Autodesk Fusion 360 part; units mm, degrees
(part 2 of 3)
sketch "SLOT - J-FRONT-02 SPIGOT (MIDDLE)" plane through (0, 0, 0) normal (0, 0, 1) x (1, 0, 0) in component "352108 FRONT - DECOR FRAME DL - RING BOTTOM - FRONT FACET"
  line L0 (-1081.329, -778.1952) -> (-1076.4372, -780.7094)
  line L1 (-1076.4372, -780.7094) -> (-1072.5517, -773.1495)
  line L2 (-1072.5517, -773.1495) -> (-1077.4434, -770.6353)
  line L3 (-1077.4434, -770.6353) -> (-1081.329, -778.1952)
  point P0 (-5000, -5000)
  dimension "d3654" = 5000
  dimension "d3655" = 5000
  dimension "d3656" = 3918.671
  dimension "d3657" = 3923.5628
  dimension "d3658" = 3927.4483
  dimension "d3659" = 3922.5566
  dimension "d3660" = 4221.8048
  dimension "d3661" = 4219.2906
  dimension "d3662" = 4226.8505
  dimension "d3663" = 4229.3647
  measures "d3654" horizontal distance of origin P0
  measures "d3655" vertical distance of origin P0
  measures "d3656" horizontal distance of L0.start P0
  measures "d3657" horizontal distance of L0.end P0
  measures "d3658" horizontal distance of L1.end P0
  measures "d3659" horizontal distance of L2.end P0
  measures "d3660" vertical distance of L0.start P0
  measures "d3661" vertical distance of L0.end P0
  measures "d3662" vertical distance of L1.end P0
  measures "d3663" vertical distance of L2.end P0
extrude "CUT - J-FRONT-02 SLOT MIDDLE" cut sketch "SLOT - J-FRONT-02 SPIGOT (MIDDLE)" along normal blind 3 from surface at 109 bodies 16 in component "352108 FRONT - DECOR FRAME DL - RING BOTTOM - FRONT FACET"
component "351101 FRONT - DECOR SKIN - DL" placed x (1, 0, 0) y (0, 1, 0) z (0, 0, 1) at (0, 0, 0)
component "351102 FRONT - DECOR BACK PLATE - DL" placed x (1, 0, 0) y (0, 1, 0) z (0, 0, 1) at (0, 0, 0)
component "351105 FRONT - DOOR HINGE-SIDE STOP - DL - PIECE 1" placed x (1, 0, 0) y (0, 1, 0) z (0, 0, 1) at (0, 0, 0)
component "351106 FRONT - DOOR HINGE-SIDE STOP - DL - PIECE 2 AND 3" placed x (1, 0, 0) y (0, 1, 0) z (0, 0, 1) at (0, 0, 0)
component "351106 FRONT - DOOR HINGE-SIDE STOP - DL - PIECE 2 AND 3" placed x (1, 0, 0) y (0, 1, 0) z (0, 0, 1) at (0, 0, 754.5)
component "351107 FRONT - DOOR HINGE-SIDE STOP - DL - PIECE 4" placed x (1, 0, 0) y (0, 1, 0) z (0, 0, 1) at (0, 0, 0)
component "368005 FRONT - FRAME-STOP SEAL - HINGE SIDE 1" placed x (1, 0, 0) y (0, 1, 0) z (0, 0, 1) at (0, 0, 0)
component "368005 FRONT - FRAME-STOP SEAL - HINGE SIDE 2 AND 3" placed x (1, 0, 0) y (0, 1, 0) z (0, 0, 1) at (0, 0, 0)
component "368005 FRONT - FRAME-STOP SEAL - HINGE SIDE 2 AND 3" placed x (1, 0, 0) y (0, 1, 0) z (0, 0, 1) at (0, 0, 754.5)
component "368005 FRONT - FRAME-STOP SEAL - HINGE SIDE 4" placed x (1, 0, 0) y (0, 1, 0) z (0, 0, 1) at (0, 0, 0)
component "351104 FRONT - DECOR FRAME - DL" placed x (1, 0, 0) y (0, 1, 0) z (0, 0, 1) at (0, 0, 0)
component "352101 FRONT - DECOR FRAME DL - BACK RING BOTTOM" placed x (1, 0, 0) y (0, 1, 0) z (0, 0, 1) at (0, 0, 0) in component "351104 FRONT - DECOR FRAME - DL"
component "352102 FRONT - DECOR FRAME DL - BACK RING DOOR SIDE" placed x (1, 0, 0) y (0, 1, 0) z (0, 0, 1) at (0, 0, 0) in component "351104 FRONT - DECOR FRAME - DL"
component "352103 FRONT - DECOR FRAME DL - BACK RING SLOPE UNDER DT" placed x (1, 0, 0) y (0, 1, 0) z (0, 0, 1) at (0, 0, 0) in component "351104 FRONT - DECOR FRAME - DL"
component "352104 FRONT - DECOR FRAME DL - BACK RING BOLT LINE" placed x (1, 0, 0) y (0, 1, 0) z (0, 0, 1) at (0, 0, 0) in component "351104 FRONT - DECOR FRAME - DL"
component "352105 FRONT - DECOR FRAME DL - RING DOOR SIDE - RINGS 1 TO 4" placed x (1, 0, 0) y (0, 1, 0) z (0, 0, 1) at (0, 0, 0) in component "351104 FRONT - DECOR FRAME - DL"
component "352106 FRONT - DECOR FRAME DL - RING BACK - RINGS 1 TO 4" placed x (1, 0, 0) y (0, 1, 0) z (0, 0, 1) at (0, 0, 0) in component "351104 FRONT - DECOR FRAME - DL"
component "352107 FRONT - DECOR FRAME DL - RING BOTTOM - OUTER FACET" placed x (1, 0, 0) y (0, 1, 0) z (0, 0, 1) at (0, 0, 0) in component "351104 FRONT - DECOR FRAME - DL"
component "352108 FRONT - DECOR FRAME DL - RING BOTTOM - FRONT FACET" placed x (1, 0, 0) y (0, 1, 0) z (0, 0, 1) at (0, 0, 0) in component "351104 FRONT - DECOR FRAME - DL"
component "352105 FRONT - DECOR FRAME DL - RING DOOR SIDE - RINGS 1 TO 4" placed x (1, 0, 0) y (0, 1, 0) z (0, 0, 1) at (0, 0, 612.25) in component "351104 FRONT - DECOR FRAME - DL"
component "352106 FRONT - DECOR FRAME DL - RING BACK - RINGS 1 TO 4" placed x (1, 0, 0) y (0, 1, 0) z (0, 0, 1) at (0, 0, 612.25) in component "351104 FRONT - DECOR FRAME - DL"
component "352109 FRONT - DECOR FRAME DL - RING OUTER FACET - RINGS 2 TO 4" placed x (1, 0, 0) y (0, 1, 0) z (0, 0, 1) at (0, 0, 0) in component "351104 FRONT - DECOR FRAME - DL"
component "352110 FRONT - DECOR FRAME DL - RING FRONT FACET - RINGS 2 TO 4" placed x (1, 0, 0) y (0, 1, 0) z (0, 0, 1) at (0, 0, 0) in component "351104 FRONT - DECOR FRAME - DL"
component "352105 FRONT - DECOR FRAME DL - RING DOOR SIDE - RINGS 1 TO 4" placed x (1, 0, 0) y (0, 1, 0) z (0, 0, 1) at (0, 0, 1366.75) in component "351104 FRONT - DECOR FRAME - DL"
component "352106 FRONT - DECOR FRAME DL - RING BACK - RINGS 1 TO 4" placed x (1, 0, 0) y (0, 1, 0) z (0, 0, 1) at (0, 0, 1366.75) in component "351104 FRONT - DECOR FRAME - DL"
component "352109 FRONT - DECOR FRAME DL - RING OUTER FACET - RINGS 2 TO 4" placed x (1, 0, 0) y (0, 1, 0) z (0, 0, 1) at (0, 0, 754.5) in component "351104 FRONT - DECOR FRAME - DL"
component "352110 FRONT - DECOR FRAME DL - RING FRONT FACET - RINGS 2 TO 4" placed x (1, 0, 0) y (0, 1, 0) z (0, 0, 1) at (0, 0, 754.5) in component "351104 FRONT - DECOR FRAME - DL"
component "352105 FRONT - DECOR FRAME DL - RING DOOR SIDE - RINGS 1 TO 4" placed x (1, 0, 0) y (0, 1, 0) z (0, 0, 1) at (0, 0, 1991.7434) in component "351104 FRONT - DECOR FRAME - DL"
component "352106 FRONT - DECOR FRAME DL - RING BACK - RINGS 1 TO 4" placed x (1, 0, 0) y (0, 1, 0) z (0, 0, 1) at (0, 0, 1991.7434) in component "351104 FRONT - DECOR FRAME - DL"
component "352109 FRONT - DECOR FRAME DL - RING OUTER FACET - RINGS 2 TO 4" placed x (1, 0, 0) y (0, 1, 0) z (0, 0, 1) at (0, 0, 1379.4934) in component "351104 FRONT - DECOR FRAME - DL"
component "352110 FRONT - DECOR FRAME DL - RING FRONT FACET - RINGS 2 TO 4" placed x (1, 0, 0) y (0, 1, 0) z (0, 0, 1) at (0, 0, 1379.4934) in component "351104 FRONT - DECOR FRAME - DL"
component "352111 FRONT - DECOR FRAME DL - HINGE POST 1" placed x (1, 0, 0) y (0, 1, 0) z (0, 0, 1) at (0, 0, 0) in component "351104 FRONT - DECOR FRAME - DL"
component "352112 FRONT - DECOR FRAME DL - DOOR-SIDE FRONT POST 1" placed x (1, 0, 0) y (0, 1, 0) z (0, 0, 1) at (0, 0, 0) in component "351104 FRONT - DECOR FRAME - DL"
component "352113 FRONT - DECOR FRAME DL - HINGE POST 2" placed x (1, 0, 0) y (0, 1, 0) z (0, 0, 1) at (0, 0, 0) in component "351104 FRONT - DECOR FRAME - DL"
component "352114 FRONT - DECOR FRAME DL - DOOR-SIDE FRONT POST 2" placed x (1, 0, 0) y (0, 1, 0) z (0, 0, 1) at (0, 0, 0) in component "351104 FRONT - DECOR FRAME - DL"
component "352115 FRONT - DECOR FRAME DL - HINGE POST 3" placed x (1, 0, 0) y (0, 1, 0) z (0, 0, 1) at (0, 0, 0) in component "351104 FRONT - DECOR FRAME - DL"
component "352116 FRONT - DECOR FRAME DL - DOOR-SIDE FRONT POST 3" placed x (1, 0, 0) y (0, 1, 0) z (0, 0, 1) at (0, 0, 0) in component "351104 FRONT - DECOR FRAME - DL"
equation "pod_w = 2500 mm" comment "SKELETON P04 DECIDED: D-01; conventions s4 (X = +-1250)"
equation "pod_d = 1700 mm" comment "SKELETON P04 DECIDED: D-01; conventions s4 (Y = +-850)"
equation "pod_h = 2400 mm" comment "SKELETON P04 DECIDED: D-21 (room floor to roof skin top)"
equation "glide_h = 10 mm" comment "SKELETON P04 ASSUMPTION: layout study inputs.py glide_h"
equation "band_h = 100 mm" comment "SKELETON P04 SOURCE: layout study B1 list B-BAND 100x40; inputs.py base_h"
equation "band_t = 40 mm" comment "SKELETON P04 SOURCE: layout study B1 list B-BAND 100x40"
equation "skin_t = 3 mm" comment "SKELETON P04 DECIDED: ACP skin, walls and ceiling (D-16; PM ruling 2026-10-31 on outer_t)"
equation "bond_t = 3 mm" comment "SKELETON P04 DECIDED: bond line between the ACP and the frame (PM ruling 2026-10-31 on outer_t)"
equation "frame_t = 40 mm" comment "SKELETON P04 DECIDED: aluminium frame tube depth, walls and ceiling (PM ruling 2026-10-31 on outer_t)"
equation "outer_t = skin_t + bond_t + frame_t" comment "SKELETON P04 DECIDED: PM ruling 2026-10-31: ACP 3 + bond line 3 + frame 40, walls and ceiling (was 43)"
equation "cav_gap = 4 mm" comment "SKELETON P04 DECIDED: D-16, D-42: the gap between the outer panel and the lining cassette in the wall and ceiling stack"
equation "cass_t = 34 mm" comment "SKELETON P04 SOURCE: layout study B1 final list L-CASS 34 (tray + 25 gap + felt 9)"
equation "stack_t = outer_t + cav_gap + cass_t" comment "SKELETON P04 CALCULATION: D-16, D-42 stack, walls and ceiling: outer panel + cavity gap + cassette (PM ruling 2026-10-31 on outer_t)"
equation "wall_depth = 1495 mm" comment "SKELETON P04 DECIDED: PM ruling pass C: side walls start at the decor back plate (Y -645), as v1 (1496)"
equation "lin_gap = 4 mm" comment "SKELETON P04 ASSUMPTION: PM ruling pass C: gap above the upper side linings so they stay floating (= the 4 mm stack gap)"
equation "seam_gap = 2.26 mm" comment "SKELETON P04 DECIDED: PM ruling 2026-10-31 (Mechanical Checker F-001, F-005): the Joints Engineer's 2.26 mm at all nine site seam types, set by a metal stop (1.5 stop washer + 0.76 rivnut head; joints register section 2.8)"
equation "mat_t = 3 mm" comment "SKELETON P04 DECIDED: D-72, PM ruling 2026-10-31 (from BASE): the 3 mm floor mat under the floor ply"
equation "floor_t = 9 mm" comment "SKELETON P04 DECIDED: PM ruling 2026-10-31: 9 mm floor panels (was 15, layout study B1 list), on the mat"
equation "thresh_h = 13 mm" comment "SKELETON P04 DECIDED: PM ruling 2026-10-31: 13 mm, a US-accessible threshold (D-18 had 20); the kick strip keeps its kick_gap above it"
equation "thresh_d = 60 mm" comment "SKELETON P04 SOURCE: layout study B1 list B-THRESH 1176 x 60 x 20"
equation "decor_d = 205 mm" comment "SKELETON P04 SOURCE: v1 geometry per the PM ruling on D-39 (as v1; the drawings win): v1 decor-frame drawing frames 191 (left) and 197 (right) deep plus ACP and back plate = the v1 STEP shell, Y -850 to -645 = 205. D-39 and the B1 list say 230-235 (v1 BOM); see BUILD-RECORD-P02"
equation "dl_w = 278 mm" comment "SKELETON P04 SOURCE: B1 list F-DL 278 (v1 BOM DL)"
equation "dr_w = 1016 mm" comment "SKELETON P04 SOURCE: B1 list F-DR 1016 (v1 STEP solid 78)"
equation "dt_w = 1697 mm" comment "SKELETON P04 SOURCE: B1 list F-DT 1697 (v1 BOM DT)"
equation "dt_h = 280 mm" comment "SKELETON P04 SOURCE: B1 list F-DT 280"
equation "door_w = 1176 mm" comment "SKELETON P04 DECIDED: D-46"
equation "door_h = 2011 mm" comment "SKELETON P04 SOURCE: B1 list F-GLASS-DOOR 2011; v1 STEP solid 238"
equation "glass_t = 8.76 mm" comment "SKELETON P04 DECIDED: D-46 (4+4 laminate)"
equation "glass_y = 699 mm" comment "SKELETON P04 SOURCE: v1 STEP solid 238 centre Y = -699 (layout study data)"
equation "kick_d = 20 mm" comment "SKELETON P04 ASSUMPTION: kick strip envelope depth (D-40 gives the height only)"
equation "kick_gap = 7 mm" comment "SKELETON P04 SOURCE: FRONT door unit: 7 mm running gap between the threshold and the kick strip for the drop seal (Mechanical Checker F-002 on P03)"
equation "fr_dz = 17 mm" comment "SKELETON P04 CALCULATION: v1 front top 2417 (v2 frame) - pod_h 2400"
equation "door_xl = 289 mm" comment "SKELETON P04 SOURCE: V1-FRONT-FACETS: door left edge X -961 = -1250 + 289"
equation "door_xbr = 1464 mm" comment "SKELETON P04 SOURCE: V1-FRONT-FACETS: door bottom-right X 214"
equation "door_xtr = 1182 mm" comment "SKELETON P04 SOURCE: V1-FRONT-FACETS: door top-right X -68"
equation "door_zb = 122 mm - fr_dz" comment "SKELETON P04 SOURCE: V1-FRONT-FACETS: door bottom Z 122"
equation "door_zt = 2133 mm - fr_dz" comment "SKELETON P04 SOURCE: V1-FRONT-FACETS: door top Z 2133"
equation "glass_gap = 4 mm" comment "SKELETON P04 DECIDED: PM ruling 2026-10-31 on Mechanical Checker F-014: the fixed glass's free edge runs parallel to the door's slanted edge, 4.0 mm away (FRONT's glass in PR #28 is the reference)"
equation "fix_xbr = 302 mm" comment "SKELETON P04 SOURCE: V1-FRONT-FACETS: fixed glass bottom-right X 948 = 1250 - 302"
equation "fix_xk = 501 mm" comment "SKELETON P04 SOURCE: V1-FRONT-FACETS: fixed glass knee X 749 = 1250 - 501"
equation "fix_zk = 1538 mm - fr_dz" comment "SKELETON P04 SOURCE: V1-FRONT-FACETS: fixed glass knee Z 1538"
equation "fix_xtr = 1480 mm" comment "SKELETON P04 SOURCE: V1-FRONT-FACETS: fixed glass top-right X 230 = -1250 + 1480"
equation "fix_zb = 119 mm - fr_dz" comment "SKELETON P04 SOURCE: V1-FRONT-FACETS: fixed glass bottom Z 119"
equation "fix_zt = 2136 mm - fr_dz" comment "SKELETON P04 SOURCE: V1-FRONT-FACETS: fixed glass top Z 2136"
equation "dt_zb = 2137 mm - fr_dz" comment "SKELETON P04 SOURCE: V1-FRONT-FACETS: DT and DR edge above the glass Z 2137"
equation "ch_zlo = 2217 mm - fr_dz" comment "SKELETON P04 SOURCE: V1-FRONT-FACETS: top chamfer front edge Z 2217 at Y -848"
equation "ch_yb = 672 mm" comment "SKELETON P04 SOURCE: V1-FRONT-FACETS: top chamfer back edge Y -672"
equation "dl_x2 = 92 mm" comment "SKELETON P04 SOURCE: V1-FRONT-FACETS: DL facet knee X -1158 = -1250 + 92"
equation "dl_y2 = 752 mm" comment "SKELETON P04 SOURCE: V1-FRONT-FACETS: DL facet knee Y -752"
equation "dl_x3 = 271 mm" comment "SKELETON P04 SOURCE: V1-FRONT-FACETS: DL front corner X -979"
equation "dl_y3 = 844 mm" comment "SKELETON P04 SOURCE: V1-FRONT-FACETS: DL front corner Y -844"
equation "dl_y1 = 670 mm" comment "SKELETON P04 SOURCE: V1-FRONT-FACETS: DL outer facet start Y -670"
equation "dl_zo = 2414 mm - fr_dz" comment "SKELETON P04 SOURCE: V1-FRONT-FACETS: DL top at the outer corner Z 2414"
equation "dt_x2 = 281 mm" comment "SKELETON P04 SOURCE: V1-FRONT-FACETS: DT lower facet left X -969 = -1250 + 281"
equation "dt_y2 = 767 mm" comment "SKELETON P04 SOURCE: V1-FRONT-FACETS: DT lower facet left Y -767"
equation "dt_y3 = 753 mm" comment "SKELETON P04 SOURCE: V1-FRONT-FACETS: DT lower facet outer Y -753 at X -1154"
equation "dr_xc = 198 mm" comment "SKELETON P04 SOURCE: V1-FRONT-FACETS: DR corner facet front X 1052 = 1250 - 198"
equation "dt_xr = 1699 mm" comment "SKELETON P04 SOURCE: V1-FRONT-FACETS: DT/DR joint at the top, X 449 = -1250 + 1699 (PM ruling pass C)"
equation "dr_yc = 672 mm" comment "SKELETON P04 SOURCE: V1-FRONT-FACETS: DR corner facet back Y -672"
equation "fix_xbl = door_xbr + ( door_zb - fix_zb ) * ( door_xbr - door_xtr ) / ( door_zt - door_zb ) + glass_gap * sqrt(( door_xbr - door_xtr ) * ( door_xbr - door_xtr ) + ( door_zt - door_zb ) * ( door_zt - door_zb )) / ( door_zt - door_zb )" comment "SKELETON P04 CALCULATION: F-014: fixed glass bottom-left, on the line glass_gap from the door's slanted edge (was v1's 1468)"
equation "fix_xtl = door_xbr + ( door_zb - fix_zt ) * ( door_xbr - door_xtr ) / ( door_zt - door_zb ) + glass_gap * sqrt(( door_xbr - door_xtr ) * ( door_xbr - door_xtr ) + ( door_zt - door_zb ) * ( door_zt - door_zb )) / ( door_zt - door_zb )" comment "SKELETON P04 CALCULATION: F-014: fixed glass top-left, on the same line (was v1's 1184)"
equation "floor_top = mat_t + floor_t" comment "SKELETON P04 CALCULATION: D-72: the floor top, Z 12 (mat 3 + ply 9); the threshold stands thresh_h above the room floor"
equation "wall_z0 = glide_h + band_h" comment "SKELETON P04 CALCULATION: base band top: glides + band"
equation "panel_z0 = wall_z0 + seam_gap" comment "SKELETON P04 CALCULATION: walls stand one seam_gap above the band top (joints register 2.8, IF-01)"
equation "wall_h = pod_h - wall_z0" comment "SKELETON P04 CALCULATION: 2290 = layout study v2_model wall_h"
equation "side_h = ( wall_h - 2 * seam_gap ) / 2" comment "SKELETON P04 CALCULATION: D-23: 2 sheets per side wall; the gap on the band and the horizontal seam (joints register 2.8)"
equation "side_l = wall_depth - seam_gap" comment "SKELETON P04 CALCULATION: side panel length along Y: the seam_gap at the decor's back plate (joints register 2.8, IF-07)"
equation "back_oh = pod_h - outer_t - seam_gap - panel_z0" comment "SKELETON P04 CALCULATION: PM ruling 2026-10-31 (pass D, F-004): the back outer frames run up to the ceiling frame (pod_h - outer_t), less the seam_gap under it, closing the slot at the back top edge"
equation "back_ph = ( back_oh - seam_gap ) / 2" comment "SKELETON P04 CALCULATION: D-23: 4 sheets on the back, two equal rows with one seam_gap between them (joints register 2.8); the lower back linings match the lower row, as on the side walls"
equation "half_pw = ( pod_w - 2 * outer_t - 3 * seam_gap ) / 2" comment "SKELETON P04 CALCULATION: SKIN width of each back and ceiling panel: two skins and three seam_gap seams between the side frames (F-001, joints register 2.8)"
equation "close_gap = 5.5 mm" comment "SKELETON P04 DECIDED: PM ruling 2026-10-31 (joints register, F-011/F-012): frame gap at the closing seams B1-B2, B3-B4 and C1-C2, which have no hard stop (slotted holes, thicker gasket)"
equation "half_fw = ( pod_w - 2 * outer_t - 2 * seam_gap - close_gap ) / 2" comment "SKELETON P04 CALCULATION: FRAME width of each back and ceiling panel: the skins overhang their frames by half_pw - half_fw at the closing seam (PM ruling 2026-10-31)"
equation "inner_w = pod_w - 2 * stack_t" comment "SKELETON P04 CALCULATION: inside width between the side linings"
equation "bolt_edge_inset = 220 mm" comment "SKELETON P04 DECIDED: PM ruling 2026-10-31: on every bolted edge the end bolts sit this far in from each panel end (the FRAME end, where the bolts go), the rest evenly spaced"
equation "spigot_inset = 100 mm" comment "SKELETON P04 DECIDED: PM ruling 2026-10-31: locating spigots this far in from each panel end (round hole at one end, slot at the other)"
equation "base_bolt_edge = bolt_edge_inset" comment "SKELETON P04 DECIDED: J-BASE-01 wall to band: the edge rule (kept by this name for parts already linked)"
equation "n_base_bolt = 4" comment "SKELETON P04 DECIDED: PM ruling 2026-10-31, J-BASE-01: bolts per panel along the band, evenly spaced"
equation "base_spigot_inset = spigot_inset" comment "SKELETON P04 DECIDED: J-BASE-01: the spigot rule (kept by this name for parts already linked)"
equation "base_side_y0 = pod_d / 2 - wall_depth + seam_gap" comment "SKELETON P04 CALCULATION: J-BASE-01: side bolt lines start at the side panel's front end (first bolt base_bolt_edge further on)"
equation "side_base_pitch = ( side_l - 2 * base_bolt_edge ) / ( n_base_bolt - 1 )" comment "SKELETON P04 CALCULATION: J-BASE-01 bolt pitch along a side panel"
equation "base_back_x0 = pod_w / 2 - outer_t - seam_gap" comment "SKELETON P04 CALCULATION: J-BASE-01: back bolt lines start at each back FRAME's outer end, X -/+ this (first bolt base_bolt_edge further in)"
equation "back_base_pitch = ( half_fw - 2 * base_bolt_edge ) / ( n_base_bolt - 1 )" comment "SKELETON P04 DECIDED: PM ruling 2026-10-31 (Reviewer 5 P2 on #58): J-BASE-01 pitch along a back panel, measured on the FRAME (half_fw), where the bolts go; 'panel end' means the frame end"
equation "ceil_bolt_z = pod_h - outer_t + frame_t / 2" comment "SKELETON P04 DECIDED: PM ruling 2026-10-31, J-CEIL-01 wall to ceiling: the bolt line on the ceiling frame's centre (Z 2374)"
equation "n_ceil_side_bolt = 4" comment "SKELETON P04 DECIDED: PM ruling 2026-10-31, J-CEIL-01: bolts along each side wall top"
equation "n_ceil_back_bolt = 4" comment "SKELETON P04 DECIDED: PM ruling 2026-10-31, J-CEIL-01: bolts along each back panel top, like the base (pitch about 253, every edge 350 or less; joints register: 82 bolts in all)"
equation "ceil_side_y0 = pod_d / 2 - wall_depth" comment "SKELETON P04 DECIDED: PM ruling 2026-10-31 (joints register): J-CEIL-01 side bolt lines start at Y -645, measured along the ceiling (first bolt bolt_edge_inset further on)"
equation "ceil_side_pitch = ( wall_depth - 2 * bolt_edge_inset ) / ( n_ceil_side_bolt - 1 )" comment "SKELETON P04 DECIDED: PM ruling 2026-10-31 (joints register): J-CEIL-01 pitch along a side wall top, over the ceiling's length (was over the side panel's)"
equation "ceil_back_x0 = pod_w / 2 - outer_t - seam_gap" comment "SKELETON P04 DECIDED: PM ruling 2026-10-31 (joints register): J-CEIL-01 back bolt lines start at each back frame's outer end, X -/+ this"
equation "ceil_back_pitch = ( half_fw - 2 * bolt_edge_inset ) / ( n_ceil_back_bolt - 1 )" comment "SKELETON P04 DECIDED: PM ruling 2026-10-31 (joints register): J-CEIL-01 pitch along a back panel top, on the frame (half_fw)"
equation "sk_ref = 5000 mm" comment "ASSUMPTION: sketch reference point offset: every sketch corner is dimensioned from a point at -sk_ref on both plane axes, so no dimension changes side when a corner crosses a pod centre line in an edit"
equation "fg_vis_zb = wall_z0" comment "CALCULATION: visible bottom of the fixed pane = the base band top (DL and DR stop there too, PM ruling 2026-10-31)"
equation "fg_vis_zt = dt_zb" comment "CALCULATION: visible top of the fixed pane = DT's underside"
equation "fg_gap = glass_gap" comment "CALCULATION: = the skeleton's glass_gap: the pane's free edge runs parallel to the door's latch edge, 4 mm off (PM ruling 2026-10-31; the skeleton's fix_xbl and fix_xtl follow the same rule since its update #58)"
equation "gu_prof_w = 15 mm" comment "SOURCE: Bohle BO5201571 aluminium U-profile 15 x 15 x 1.5 (hardware selection C5)"
equation "gu_prof_d = 15 mm" comment "SOURCE: as gu_prof_w"
equation "gu_prof_t = 1.5 mm" comment "SOURCE: as gu_prof_w"
equation "gu_w = gu_prof_w - 2 * gu_prof_t" comment "CALCULATION: inner width of the U-profile = the U-seal's outer width"
equation "gu_base = 2 mm" comment "ASSUMPTION: U-seal base under the glass edge; HOLD for Bohle's BO5201735 section drawing"
equation "gu_in_d = gu_prof_d - gu_prof_t" comment "CALCULATION: inner depth of the U-profile"
equation "fg_bite = gu_in_d - gu_base" comment "CALCULATION: glass cover in the hidden channels, 11.5 (PM ruling 2026-10-31); HOLD for the glass supplier's minimum"
equation "fg_r_len = sqrt(( fix_xbr - fix_xk ) * ( fix_xbr - fix_xk ) + ( fix_zk - fix_zb ) * ( fix_zk - fix_zb ))" comment "CALCULATION: length of the skeleton's right edge (bottom-right corner to the knee)"
equation "fg_rnx = ( fix_zk - fix_zb ) / fg_r_len" comment "CALCULATION: right edge outward normal, X"
equation "fg_rnz = ( fix_xk - fix_xbr ) / fg_r_len" comment "CALCULATION: right edge outward normal, Z"
equation "fg_rc = fg_rnx * ( pod_w / 2 - fix_xbr ) + fg_rnz * fix_zb" comment "CALCULATION: right edge line constant"
equation "fg_d_len = sqrt(( pod_w - fix_xtr - fix_xk ) * ( pod_w - fix_xtr - fix_xk ) + ( dt_zb - fix_zk ) * ( dt_zb - fix_zk ))" comment "CALCULATION: length of DR's diagonal inner edge (knee to DT's underside at X -pod_w/2 + fix_xtr)"
equation "fg_dnx = ( dt_zb - fix_zk ) / fg_d_len" comment "CALCULATION: diagonal outward normal, X"
equation "fg_dnz = ( pod_w - fix_xtr - fix_xk ) / fg_d_len" comment "CALCULATION: diagonal outward normal, Z"
equation "fg_dc = fg_dnx * ( pod_w / 2 - fix_xk ) + fg_dnz * fix_zk" comment "CALCULATION: diagonal line constant"
equation "fg_det = fg_rnx * fg_dnz - fg_rnz * fg_dnx" comment "CALCULATION: for the knee corner"
equation "fg_l_len = sqrt(( door_xbr - door_xtr ) * ( door_xbr - door_xtr ) + ( door_zt - door_zb ) * ( door_zt - door_zb ))" comment "CALCULATION: length of the door's latch edge"
equation "fg_lnx = ( door_zt - door_zb ) / fg_l_len" comment "CALCULATION: door latch edge normal toward the pane, X"
equation "fg_lnz = ( door_xbr - door_xtr ) / fg_l_len" comment "CALCULATION: door latch edge normal toward the pane, Z"
equation "fg_lc = fg_lnx * ( -pod_w / 2 + door_xbr ) + fg_lnz * door_zb" comment "CALCULATION: door latch edge line constant"
equation "jf_x = pod_w / 2 - skin_t - bond_t - frame_t / 2" comment "CALCULATION: joints register J-FRONT-01: the side panel's front member centre line, X -/+1224 (skin, bond line and half the 40 frame in from the outside, skeleton named values)"
equation "jf_hole = 9.53 mm" comment "SOURCE: rivnut 838003 (Sherex CAH2-610-4.2, zinc-plated steel, D-131) hole 9.53 +0.10/0, as the aluminium part's (joints register H-03; unverified for the steel part, HOLD-04)"
equation "jf_z1 = panel_z0 + bolt_edge_inset" comment "CALCULATION: lower panel, bottom bolt (220 rule)"
equation "jf_z2 = panel_z0 + side_h / 2" comment "CALCULATION: lower panel, middle bolt"
equation "jf_z3 = panel_z0 + side_h - bolt_edge_inset" comment "CALCULATION: lower panel, top bolt"
equation "jf_z4 = panel_z0 + side_h + seam_gap + bolt_edge_inset" comment "CALCULATION: upper panel, bottom bolt"
equation "jf_z5 = panel_z0 + side_h + seam_gap + side_h / 2" comment "CALCULATION: upper panel, middle bolt"
equation "jf_z6 = panel_z0 + 2 * side_h + seam_gap - bolt_edge_inset" comment "CALCULATION: upper panel, top bolt"
equation "dl_skin_t = 3 mm" comment "SOURCE: ACP 3 mm, EV3038 Dark Yellow (D-12; hardware selection A1)"
equation "dl_fo = dl_skin_t + bond_t" comment "CALCULATION: a frame tube's face from the skin's outer face: the 3 mm ACP and the 3 mm bond line (skeleton bond_t; the bond spec's joint, at least 12 wide x 3 thick, D-137), so every tube that bonds to the skin stands 3 mm off it (PM ruling 2026-11-01)"
equation "dl_back_t = 2 mm" comment "SOURCE: joints register J-FRONT-01: the back plate is aluminium 1.0 to 2.7 thick at each bolt, for the rivnuts (HOLD-10)"
equation "door_top_cut = 2 mm" comment "DECIDED: PM ruling 2026-10-31: the leaf 2 mm short of the skeleton top (catch gap)"
equation "leaf_zt = door_zt - door_top_cut" comment "CALCULATION: top of the door leaf"
equation "hinge_clamp_h = 120 mm" comment "ASSUMPTION: reserved height per hinge; HOLD H01 (as the door unit)"
equation "hinge_clamp_t = 40 mm" comment "ASSUMPTION: reserved thickness across the glass; HOLD H01 (as the door unit)"
equation "hinge_pocket_d = 160 mm" comment "SOURCE: the HOLD candidate's 160 mm frame pocket in DL (D-30, D-46)"
equation "hinge_x0 = -pod_w / 2 + dl_w - hinge_pocket_d" comment "CALCULATION: inner end of the hinge pocket"
equation "hinge_z1 = door_zb + 250 mm" comment "ASSUMPTION: as the door unit; HOLD H01"
equation "hinge_z3 = leaf_zt - 250 mm" comment "ASSUMPTION: as the door unit; HOLD H01"
equation "hinge_z2 = ( hinge_z1 + hinge_z3 ) / 2" comment "ASSUMPTION: as the door unit; HOLD H01"
equation "hinge_clear = 2 mm" comment "ASSUMPTION: the pocket's clearance round the hinge space"
equation "stop_gap = 4 mm" comment "SOURCE: athmer PS 1515 P Flex works in a 2 to 6 mm frame gap (selection C3): 4 nominal"
equation "ps_s = 15 mm" comment "SOURCE: athmer PS 1515 P Flex, 15 x 15 (selection C3)"
equation "stop_t = 2 mm" comment "ASSUMPTION: stop: an aluminium angle leg 2 thick on DL's door-side face"
equation "stop_reach = 30 mm" comment "SOURCE: the stop: a standard 30 x 20 x 2 aluminium angle (EN 755-9); its leg reaches from DL's face across the 11 mm gap and 19 over the glass, past the 15 mm seal"
equation "hinge_skip = 10 mm" comment "ASSUMPTION: the stop and seal stop 10 short of each hinge space"
equation "dt_stop_h = 20 mm" comment "SOURCE: DT's top stop leg hangs 20 below DT's underside (its 20 x 20 x 2 angle)"
equation "stop_fl = 20 mm" comment "SOURCE: the stop's flange on DL's door-side face (the 30 x 20 x 2 angle), bonded with structural tape (product HOLD)"
equation "fr_w = 20 mm" comment "CALCULATION: frame tube 20 x 20 x 1.5, 6063-T6 (D-79), as DR and DT"
equation "fr_t = 1.5 mm" comment "CALCULATION: frame tube wall, as fr_w"
equation "fr_wb = 60 mm" comment "ASSUMPTION: bolt-line post 60 x 20 x 1.5 behind the back plate: the J-FRONT-01 rivnut tails go into it through 14 mm holes (HOLD-10), mirror of DR's"
equation "fr_wh = 60 mm" comment "ASSUMPTION: hinge post 60 x 20 x 1.5 behind the three hinge pockets, 60 across the glass plane, as v1's 60 x 20 members: the hinges' frame halves screw into it (holes when the hinge is named, HOLD H01)"
equation "fr_hole_jf = 14 mm" comment "CALCULATION: hole round each J-FRONT-01 rivnut in the bolt-line post, as DR"
equation "dl_m = ( dl_zo - dt_zb ) / dl_w" comment "CALCULATION: rise of the slope DT sits on, per unit of X"
equation "dl_k = sqrt(1 + dl_m * dl_m)" comment "CALCULATION: for pushing the slope line in"
equation "dl_l1 = sqrt(dl_x2 * dl_x2 + ( dl_y2 - dl_y1 ) * ( dl_y2 - dl_y1 ))" comment "CALCULATION: outer facet length in plan"
equation "dl_l2 = sqrt(( dl_x3 - dl_x2 ) * ( dl_x3 - dl_x2 ) + ( dl_y3 - dl_y2 ) * ( dl_y3 - dl_y2 ))" comment "CALCULATION: front facet length in plan"
equation "fr_z2 = ( hinge_z1 + hinge_z2 ) / 2 - fr_w / 2" comment "CALCULATION: ring between hinges 1 and 2"
equation "fr_z3 = ( hinge_z2 + hinge_z3 ) / 2 - fr_w / 2" comment "CALCULATION: ring between hinges 2 and 3"
equation "fr_z4 = dt_zb + dl_m * dl_fo - dl_skin_t * dl_k - fr_w" comment "CALCULATION: top ring, its top a skin thickness under the slope (DT's skin rests on DL's skins there, D-152) at the door-side tube's outer face, which stands the bond line off the door-side skin"
equation "sp_c = dl_fo + fr_w / 2" comment "CALCULATION: the bottom ring tube's centre line, in from the outer faces"
equation "sp_e = 100 mm" comment "SOURCE: R-J13: spigots 100 in from the ends of the edge a part is set down on"
equation "sp_hole = 8.5 mm" comment "SOURCE: R-J13: spigot hole 8.5 round at one end, 8.5 x 14 slot at the other"
equation "sp_slot = 14 mm" comment "SOURCE: R-J13: the slot 14 long along the edge"
equation "sp_skin = 16 mm" comment "CALCULATION: clearance in the bottom skin round each spigot's rivnut head (12.96)"
equation "sp_d1x = dl_x2 / dl_l1" comment "CALCULATION: outer facet direction, X"
equation "sp_d1y = -( dl_y2 - dl_y1 ) / dl_l1" comment "CALCULATION: outer facet direction, Y"
equation "sp_n1x = ( dl_y2 - dl_y1 ) / dl_l1" comment "CALCULATION: outer facet normal into DL, X"
equation "sp_n1y = dl_x2 / dl_l1" comment "CALCULATION: outer facet normal into DL, Y"
equation "sp_d2x = ( dl_x3 - dl_x2 ) / dl_l2" comment "CALCULATION: front facet direction, X"
equation "sp_d2y = -( dl_y3 - dl_y2 ) / dl_l2" comment "CALCULATION: front facet direction, Y"
equation "sp_n2x = ( dl_y3 - dl_y2 ) / dl_l2" comment "CALCULATION: front facet normal into DL, X"
equation "sp_n2y = ( dl_x3 - dl_x2 ) / dl_l2" comment "CALCULATION: front facet normal into DL, Y"
equation "sp_tk = sp_c * ( 1 - sp_n1x ) / sp_d1x" comment "CALCULATION: the knee on the ring's centre line, along the outer facet"
equation "sp_side = ( -pod_d / 2 + decor_d ) - ( -dl_y1 + sp_d1y * sp_tk + sp_c * sp_n1y )" comment "CALCULATION: the bottom edge's run along the side, from the back to the knee"
equation "sp_ta = sp_tk + sp_e - sp_side" comment "CALCULATION: the round hole, along the outer facet from its corner"
equation "sp_ax = -pod_w / 2 + sp_d1x * sp_ta + sp_c * sp_n1x" comment "CALCULATION: the round hole, X (-1172.7)"
equation "sp_ay = -dl_y1 + sp_d1y * sp_ta + sp_c * sp_n1y" comment "CALCULATION: the round hole, Y (-717.5)"
equation "sp_te = ( dl_w - sp_c - dl_x2 - sp_c * sp_n2x ) / sp_d2x" comment "CALCULATION: the front facet's end at the door side, on the ring's centre line"
equation "sp_bx = -pod_w / 2 + dl_x2 + sp_d2x * ( sp_te - sp_e ) + sp_c * sp_n2x" comment "CALCULATION: the slot's centre, X (-1076.9)"
equation "sp_by = -dl_y2 + sp_d2y * ( sp_te - sp_e ) + sp_c * sp_n2y" comment "CALCULATION: the slot's centre, Y (-775.7)"
equation "d3208 = sk_ref"
equation "d3209 = sk_ref"
equation "d3210 = ( -pod_w / 2 ) + sk_ref"
equation "d3211 = ( -pod_w / 2 + dl_x2 ) + sk_ref"
equation "d3212 = ( -pod_w / 2 + dl_x3 ) + sk_ref"
equation "d3213 = ( -pod_w / 2 + dl_w ) + sk_ref"
equation "d3214 = ( -dl_y1 ) + sk_ref"
equation "d3215 = ( -dl_y2 ) + sk_ref"
equation "d3216 = ( -dl_y3 ) + sk_ref"
equation "d3217 = ( -pod_d / 2 + decor_d ) + sk_ref"
equation "d3218 = ( wall_z0 ) * ( 1 )"
equation "d3219 = ( pod_h ) - ( wall_z0 )"
equation "d3221 = sk_ref"
equation "d3222 = sk_ref"
equation "d3223 = ( -pod_w / 2 + dl_w ) + sk_ref"
equation "d3224 = ( -pod_w / 2 ) + sk_ref"
equation "d3225 = ( dl_zo ) + sk_ref"
equation "d3226 = ( dt_zb ) + sk_ref"
equation "d3227 = ( pod_h ) + sk_ref"
equation "d3228 = ( -pod_d / 2 ) * ( 1 )"
equation "d3229 = ( -pod_d / 2 + decor_d ) - ( -pod_d / 2 )"
equation "d3231 = dl_skin_t"
equation "d3232 = sk_ref"
equation "d3233 = sk_ref"
equation "d3234 = ( -pod_w / 2 + dl_w + 1 mm ) + sk_ref"
equation "d3235 = ( hinge_x0 - hinge_clear ) + sk_ref"
equation "d3236 = ( -glass_y - hinge_clamp_t / 2 - hinge_clear ) + sk_ref"
equation "d3237 = ( -glass_y + hinge_clamp_t / 2 + hinge_clear ) + sk_ref"
equation "d3238 = ( hinge_z1 - hinge_clamp_h / 2 - hinge_clear ) * ( 1 )"
equation "d3239 = ( hinge_z1 + hinge_clamp_h / 2 + hinge_clear ) - ( hinge_z1 - hinge_clamp_h / 2 - hinge_clear )"
equation "d3241 = sk_ref"
equation "d3242 = sk_ref"
equation "d3243 = ( -pod_w / 2 + dl_w + 1 mm ) + sk_ref"
equation "d3244 = ( hinge_x0 - hinge_clear ) + sk_ref"
equation "d3245 = ( -glass_y - hinge_clamp_t / 2 - hinge_clear ) + sk_ref"
equation "d3246 = ( -glass_y + hinge_clamp_t / 2 + hinge_clear ) + sk_ref"
equation "d3247 = ( hinge_z2 - hinge_clamp_h / 2 - hinge_clear ) * ( 1 )"
equation "d3248 = ( hinge_z2 + hinge_clamp_h / 2 + hinge_clear ) - ( hinge_z2 - hinge_clamp_h / 2 - hinge_clear )"
equation "d3250 = sk_ref"
equation "d3251 = sk_ref"
equation "d3252 = ( -pod_w / 2 + dl_w + 1 mm ) + sk_ref"
equation "d3253 = ( hinge_x0 - hinge_clear ) + sk_ref"
equation "d3254 = ( -glass_y - hinge_clamp_t / 2 - hinge_clear ) + sk_ref"
equation "d3255 = ( -glass_y + hinge_clamp_t / 2 + hinge_clear ) + sk_ref"
equation "d3256 = ( hinge_z3 - hinge_clamp_h / 2 - hinge_clear ) * ( 1 )"
equation "d3257 = ( hinge_z3 + hinge_clamp_h / 2 + hinge_clear ) - ( hinge_z3 - hinge_clamp_h / 2 - hinge_clear )"
equation "d3259 = sk_ref"
equation "d3260 = sk_ref"
equation "d3261 = ( -pod_w / 2 + dl_w - dl_skin_t ) + sk_ref"
equation "d3262 = ( -pod_w / 2 + dl_skin_t ) + sk_ref"
equation "d3263 = ( wall_z0 + dl_skin_t ) + sk_ref"
equation "d3264 = ( ( dl_zo + ( dt_zb - dl_zo ) * ( ( -pod_w / 2 + dl_w - dl_skin_t ) - ( -pod_w / 2 ) ) / dl_w ) ) + sk_ref"
equation "d3265 = ( ( dl_zo + ( dt_zb - dl_zo ) * ( ( -pod_w / 2 + dl_skin_t ) - ( -pod_w / 2 ) ) / dl_w ) ) + sk_ref"
equation "d3266 = ( -pod_d / 2 + decor_d - dl_back_t ) * ( 1 )"
equation "d3267 = ( -pod_d / 2 + decor_d ) - ( -pod_d / 2 + decor_d - dl_back_t )"
equation "d3269 = sk_ref"
equation "d3270 = sk_ref"
equation "d3271 = ( -jf_x ) + sk_ref"
equation "d3272 = ( jf_z1 ) + sk_ref"
equation "d3273 = jf_hole"
equation "d3274 = ( -jf_x ) + sk_ref"
equation "d3275 = ( jf_z2 ) + sk_ref"
equation "d3276 = jf_hole"
equation "d3277 = ( -jf_x ) + sk_ref"
equation "d3278 = ( jf_z3 ) + sk_ref"
equation "d3279 = jf_hole"
equation "d3280 = ( -jf_x ) + sk_ref"
equation "d3281 = ( jf_z4 ) + sk_ref"
equation "d3282 = jf_hole"
equation "d3283 = ( -jf_x ) + sk_ref"
equation "d3284 = ( jf_z5 ) + sk_ref"
equation "d3285 = jf_hole"
equation "d3286 = ( -jf_x ) + sk_ref"
equation "d3287 = ( jf_z6 ) + sk_ref"
equation "d3288 = jf_hole"
equation "d3289 = ( -pod_d / 2 + decor_d - dl_back_t - 1 mm ) * ( 1 )"
equation "d3290 = ( -pod_d / 2 + decor_d + 1 mm ) - ( -pod_d / 2 + decor_d - dl_back_t - 1 mm )"
equation "d3292 = sk_ref"
equation "d3293 = sk_ref"
equation "d3294 = ( -pod_w / 2 + dl_w + stop_reach ) + sk_ref"
equation "d3295 = ( -pod_w / 2 + dl_w + stop_t ) + sk_ref"
equation "d3296 = ( -pod_w / 2 + dl_w ) + sk_ref"
equation "d3297 = ( ( -glass_y + glass_t / 2 + stop_gap ) ) + sk_ref"
equation "d3298 = ( ( -glass_y + glass_t / 2 + stop_gap ) + stop_t ) + sk_ref"
equation "d3299 = ( ( -glass_y + glass_t / 2 + stop_gap ) + stop_fl ) + sk_ref"
equation "d3300 = ( door_zb ) * ( 1 )"
equation "d3301 = ( hinge_z1 - hinge_clamp_h / 2 - hinge_skip ) - ( door_zb )"
equation "d3303 = sk_ref"
equation "d3304 = sk_ref"
equation "d3305 = ( -pod_w / 2 + dl_w + stop_reach ) + sk_ref"
equation "d3306 = ( -pod_w / 2 + dl_w + stop_t ) + sk_ref"
equation "d3307 = ( -pod_w / 2 + dl_w ) + sk_ref"
equation "d3308 = ( ( -glass_y + glass_t / 2 + stop_gap ) ) + sk_ref"
equation "d3309 = ( ( -glass_y + glass_t / 2 + stop_gap ) + stop_t ) + sk_ref"
equation "d3310 = ( ( -glass_y + glass_t / 2 + stop_gap ) + stop_fl ) + sk_ref"
equation "d3311 = ( hinge_z1 + hinge_clamp_h / 2 + hinge_skip ) * ( 1 )"
equation "d3312 = ( hinge_z2 - hinge_clamp_h / 2 - hinge_skip ) - ( hinge_z1 + hinge_clamp_h / 2 + hinge_skip )"
equation "d3314 = ( hinge_z2 + hinge_clamp_h / 2 + hinge_skip ) - ( hinge_z1 + hinge_clamp_h / 2 + hinge_skip )"
equation "d3320 = sk_ref"
equation "d3321 = sk_ref"
equation "d3322 = ( -pod_w / 2 + dl_w + stop_reach ) + sk_ref"
equation "d3323 = ( -pod_w / 2 + dl_w + stop_t ) + sk_ref"
equation "d3324 = ( -pod_w / 2 + dl_w ) + sk_ref"
equation "d3325 = ( ( -glass_y + glass_t / 2 + stop_gap ) ) + sk_ref"
equation "d3326 = ( ( -glass_y + glass_t / 2 + stop_gap ) + stop_t ) + sk_ref"
equation "d3327 = ( ( -glass_y + glass_t / 2 + stop_gap ) + stop_fl ) + sk_ref"
equation "d3328 = ( hinge_z3 + hinge_clamp_h / 2 + hinge_skip ) * ( 1 )"
equation "d3329 = ( dt_zb - dt_stop_h ) - ( hinge_z3 + hinge_clamp_h / 2 + hinge_skip )"
equation "d3331 = sk_ref"
equation "d3332 = sk_ref"
equation "d3333 = ( -pod_w / 2 + door_xl + ps_s ) + sk_ref"
equation "d3334 = ( -pod_w / 2 + door_xl ) + sk_ref"
equation "d3335 = ( -glass_y + glass_t / 2 ) + sk_ref"
equation "d3336 = ( -glass_y + glass_t / 2 + stop_gap ) + sk_ref"
equation "d3337 = ( door_zb ) * ( 1 )"
equation "d3338 = ( hinge_z1 - hinge_clamp_h / 2 - hinge_skip ) - ( door_zb )"
equation "d3340 = sk_ref"
equation "d3341 = sk_ref"
equation "d3342 = ( -pod_w / 2 + door_xl + ps_s ) + sk_ref"
equation "d3343 = ( -pod_w / 2 + door_xl ) + sk_ref"
equation "d3344 = ( -glass_y + glass_t / 2 ) + sk_ref"
equation "d3345 = ( -glass_y + glass_t / 2 + stop_gap ) + sk_ref"
equation "d3346 = ( hinge_z1 + hinge_clamp_h / 2 + hinge_skip ) * ( 1 )"
equation "d3347 = ( hinge_z2 - hinge_clamp_h / 2 - hinge_skip ) - ( hinge_z1 + hinge_clamp_h / 2 + hinge_skip )"
equation "d3349 = ( hinge_z2 + hinge_clamp_h / 2 + hinge_skip ) - ( hinge_z1 + hinge_clamp_h / 2 + hinge_skip )"
equation "d3355 = sk_ref"
equation "d3356 = sk_ref"
equation "d3357 = ( -pod_w / 2 + door_xl + ps_s ) + sk_ref"
equation "d3358 = ( -pod_w / 2 + door_xl ) + sk_ref"
equation "d3359 = ( -glass_y + glass_t / 2 ) + sk_ref"
equation "d3360 = ( -glass_y + glass_t / 2 + stop_gap ) + sk_ref"
equation "d3361 = ( hinge_z3 + hinge_clamp_h / 2 + hinge_skip ) * ( 1 )"
equation "d3362 = ( dt_zb - ps_s ) - ( hinge_z3 + hinge_clamp_h / 2 + hinge_skip )"
equation "d3364 = sk_ref"
equation "d3365 = sk_ref"
equation "d3366 = ( ( ( -pod_w / 2 + dl_fo ) ) ) + sk_ref"
equation "d3367 = ( ( -( ( -( -pod_w / 2 + dl_w ) + dl_fo ) ) ) ) + sk_ref"
equation "d3368 = ( ( -( ( -( -pod_w / 2 + dl_w ) + dl_fo + fr_w ) ) ) ) + sk_ref"
equation "d3369 = ( ( ( -pod_w / 2 + dl_fo + fr_wb ) ) ) + sk_ref"
equation "d3370 = ( ( wall_z0 ) ) + sk_ref"
equation "d3371 = ( ( -( -( ( wall_z0 + 0 mm + fr_w ) ) ) ) ) + sk_ref"
equation "d3372 = ( ( -pod_d / 2 + decor_d - dl_back_t - fr_w ) ) * ( 1 )"
equation "d3373 = ( ( -pod_d / 2 + decor_d - dl_back_t ) ) - ( ( -pod_d / 2 + decor_d - dl_back_t - fr_w ) )"
equation "d3375 = fr_t"
equation "d3376 = sk_ref"
equation "d3377 = sk_ref"
equation "d3378 = ( ( -( ( -( -pod_w / 2 + dl_w ) + dl_fo ) ) ) ) + sk_ref"
equation "d3379 = ( ( ( ( ( -( -pod_w / 2 + dl_w ) + dl_fo + fr_w ) ) * ( -1 / dl_k ) ) / ( -( -1 / dl_k ) ) ) ) + sk_ref"
equation "d3380 = ( ( -( -wall_z0 ) ) ) + sk_ref"
equation "d3381 = ( ( ( -( ( -( dt_zb + dl_m * ( -pod_w / 2 + dl_w ) ) / dl_k + dl_skin_t ) ) - ( ( -dl_m / dl_k ) * ( ( -( -pod_w / 2 + dl_w ) + dl_fo ) ) ) ) / ( -( -1 / dl_k ) ) ) ) + sk_ref"
equation "d3382 = ( ( ( -( ( -( dt_zb + dl_m * ( -pod_w / 2 + dl_w ) ) / dl_k + dl_skin_t + fr_w ) ) - ( ( -dl_m / dl_k ) * ( ( -( -pod_w / 2 + dl_w ) + dl_fo + fr_w ) ) ) ) / ( -( -1 / dl_k ) ) ) ) + sk_ref"
equation "d3383 = ( ( -( -( ( wall_z0 + 0 mm + fr_w ) ) ) ) ) + sk_ref"
equation "d3384 = ( ( -pod_d / 2 + decor_d - dl_back_t - fr_w ) ) * ( 1 )"
equation "d3385 = ( ( -pod_d / 2 + decor_d - dl_back_t ) ) - ( ( -pod_d / 2 + decor_d - dl_back_t - fr_w ) )"
equation "d3387 = fr_t"
equation "d3388 = sk_ref"
equation "d3389 = sk_ref"
equation "d3390 = ( ( ( ( ( -( -pod_w / 2 + dl_w ) + dl_fo ) ) * ( -1 / dl_k ) ) / ( -( -1 / dl_k ) ) ) ) + sk_ref"
equation "d3391 = ( ( ( -( ( ( -pod_w / 2 + dl_fo ) ) * ( -1 / dl_k ) ) ) / ( -( -1 / dl_k ) ) ) ) + sk_ref"
equation "d3392 = ( ( ( -( ( ( -pod_w / 2 + dl_fo + fr_wb ) ) * ( -1 / dl_k ) ) ) / ( -( -1 / dl_k ) ) ) ) + sk_ref"
equation "d3393 = ( ( ( ( ( -( -pod_w / 2 + dl_w ) + dl_fo + fr_w ) ) * ( -1 / dl_k ) ) / ( -( -1 / dl_k ) ) ) ) + sk_ref"
equation "d3394 = ( ( ( -( ( -( dt_zb + dl_m * ( -pod_w / 2 + dl_w ) ) / dl_k + dl_skin_t ) ) - ( ( -dl_m / dl_k ) * ( ( -( -pod_w / 2 + dl_w ) + dl_fo ) ) ) ) / ( -( -1 / dl_k ) ) ) ) + sk_ref"
equation "d3395 = ( ( ( ( -dl_m / dl_k ) * ( ( -pod_w / 2 + dl_fo ) ) - ( ( -( dt_zb + dl_m * ( -pod_w / 2 + dl_w ) ) / dl_k + dl_skin_t ) ) ) / ( -( -1 / dl_k ) ) ) ) + sk_ref"
equation "d3396 = ( ( ( ( -dl_m / dl_k ) * ( ( -pod_w / 2 + dl_fo + fr_wb ) ) - ( ( -( dt_zb + dl_m * ( -pod_w / 2 + dl_w ) ) / dl_k + dl_skin_t + fr_w ) ) ) / ( -( -1 / dl_k ) ) ) ) + sk_ref"
equation "d3397 = ( ( ( -( ( -( dt_zb + dl_m * ( -pod_w / 2 + dl_w ) ) / dl_k + dl_skin_t + fr_w ) ) - ( ( -dl_m / dl_k ) * ( ( -( -pod_w / 2 + dl_w ) + dl_fo + fr_w ) ) ) ) / ( -( -1 / dl_k ) ) ) ) + sk_ref"
equation "d3398 = ( ( -pod_d / 2 + decor_d - dl_back_t - fr_w ) ) * ( 1 )"
equation "d3399 = ( ( -pod_d / 2 + decor_d - dl_back_t ) ) - ( ( -pod_d / 2 + decor_d - dl_back_t - fr_w ) )"
equation "d3401 = fr_t"
equation "d3402 = sk_ref"
equation "d3403 = sk_ref"
equation "d3404 = ( ( ( -( ( ( -pod_w / 2 + dl_fo ) ) * ( -1 / dl_k ) ) ) / ( -( -1 / dl_k ) ) ) ) + sk_ref"
equation "d3405 = ( ( ( -pod_w / 2 + dl_fo + fr_wb ) ) ) + sk_ref"
equation "d3406 = ( ( ( ( -dl_m / dl_k ) * ( ( -pod_w / 2 + dl_fo ) ) - ( ( -( dt_zb + dl_m * ( -pod_w / 2 + dl_w ) ) / dl_k + dl_skin_t ) ) ) / ( -( -1 / dl_k ) ) ) ) + sk_ref"
equation "d3407 = ( ( wall_z0 ) ) + sk_ref"
equation "d3408 = ( ( ( wall_z0 + 0 mm + fr_w ) ) ) + sk_ref"
equation "d3409 = ( ( ( ( -dl_m / dl_k ) * ( ( -pod_w / 2 + dl_fo + fr_wb ) ) - ( ( -( dt_zb + dl_m * ( -pod_w / 2 + dl_w ) ) / dl_k + dl_skin_t + fr_w ) ) ) / ( -( -1 / dl_k ) ) ) ) + sk_ref"
equation "d3410 = ( ( -pod_d / 2 + decor_d - dl_back_t - fr_w ) ) * ( 1 )"
equation "d3411 = ( ( -pod_d / 2 + decor_d - dl_back_t ) ) - ( ( -pod_d / 2 + decor_d - dl_back_t - fr_w ) )"
equation "d3413 = fr_t"
equation "d3414 = sk_ref"
equation "d3415 = sk_ref"
equation "d3416 = ( ( ( ( ( -( -pod_w / 2 + dl_w ) + dl_fo ) ) * ( ( dl_x3 - dl_x2 ) / dl_l2 ) ) / ( -( ( dl_x3 - dl_x2 ) / dl_l2 ) ) ) ) + sk_ref"
equation "d3417 = ( ( -( ( -( -pod_w / 2 + dl_w ) + dl_fo + fr_w ) ) ) ) + sk_ref"
equation "d3418 = ( ( ( -( ( ( dl_y3 - dl_y2 ) / dl_l2 * ( -pod_w / 2 + dl_x2 ) + ( dl_x3 - dl_x2 ) / dl_l2 * ( -dl_y2 ) + dl_fo ) ) - ( ( ( dl_y3 - dl_y2 ) / dl_l2 ) * ( ( -( -pod_w / 2 + dl_w ) + dl_fo ) ) ) ) / ( -( ( dl_x3 - dl_x2 ) / dl_l2 ) ) ) ) + sk_ref"
equation "d3419 = ( ( -dl_y1 ) ) + sk_ref"
equation "d3420 = ( ( -( ( dl_y1 + fr_w ) ) ) ) + sk_ref"
equation "d3421 = ( ( ( ( ( dl_y3 - dl_y2 ) / dl_l2 ) * ( ( -( -pod_w / 2 + dl_w ) + dl_fo + fr_w ) ) - ( -( ( ( dl_y3 - dl_y2 ) / dl_l2 * ( -pod_w / 2 + dl_x2 ) + ( dl_x3 - dl_x2 ) / dl_l2 * ( -dl_y2 ) + dl_fo ) ) ) ) / ( -( -( ( dl_x3 - dl_x2 ) / dl_l2 ) ) ) ) ) + sk_ref"
equation "d3422 = ( wall_z0 ) * ( 1 )"
equation "d3423 = ( wall_z0 + fr_w ) - ( wall_z0 )"
equation "d3425 = fr_t"
equation "d3426 = sk_ref"
equation "d3427 = sk_ref"
equation "d3428 = ( ( -( ( -( -pod_w / 2 + dl_w ) + dl_fo ) ) ) ) + sk_ref"
equation "d3429 = ( ( ( dl_y1 * ( dl_x2 / dl_l1 ) - ( -( ( ( dl_y2 - dl_y1 ) / dl_l1 * ( -pod_w / 2 ) + dl_x2 / dl_l1 * ( -dl_y1 ) + dl_fo ) ) ) ) / ( -( -( ( dl_y2 - dl_y1 ) / dl_l1 ) ) ) ) ) + sk_ref"
equation "d3430 = ( ( ( ( ( dl_y1 + fr_w ) ) * ( dl_x2 / dl_l1 ) - ( -( ( ( dl_y2 - dl_y1 ) / dl_l1 * ( -pod_w / 2 ) + dl_x2 / dl_l1 * ( -dl_y1 ) + dl_fo + fr_w ) ) ) ) / ( -( -( ( dl_y2 - dl_y1 ) / dl_l1 ) ) ) ) ) + sk_ref"
equation "d3431 = ( ( -( ( -( -pod_w / 2 + dl_w ) + dl_fo + fr_w ) ) ) ) + sk_ref"
equation "d3432 = ( ( -dl_y1 ) ) + sk_ref"
equation "d3433 = ( ( ( -( ( ( dl_y2 - dl_y1 ) / dl_l1 ) * ( ( dl_y1 + fr_w ) ) ) ) / ( -( -( ( dl_y2 - dl_y1 ) / dl_l1 ) ) ) ) ) + sk_ref"
equation "d3434 = ( wall_z0 ) * ( 1 )"
equation "d3435 = ( wall_z0 + fr_w ) - ( wall_z0 )"
equation "d3437 = fr_t"
equation "d3438 = sk_ref"
equation "d3439 = sk_ref"
equation "d3440 = ( ( ( dl_y1 * ( dl_x2 / dl_l1 ) - ( -( ( ( dl_y2 - dl_y1 ) / dl_l1 * ( -pod_w / 2 ) + dl_x2 / dl_l1 * ( -dl_y1 ) + dl_fo ) ) ) ) / ( -( -( ( dl_y2 - dl_y1 ) / dl_l1 ) ) ) ) ) + sk_ref"
equation "d3441 = ( ( ( ( ( ( dl_y2 - dl_y1 ) / dl_l1 * ( -pod_w / 2 ) + dl_x2 / dl_l1 * ( -dl_y1 ) + dl_fo ) ) * ( ( dl_x3 - dl_x2 ) / dl_l2 ) - ( ( ( ( dl_y3 - dl_y2 ) / dl_l2 * ( -pod_w / 2 + dl_x2 ) + ( dl_x3 - dl_x2 ) / dl_l2 * ( -dl_y2 ) + dl_fo ) ) * ( dl_x2 / dl_l1 ) ) ) / ( ( ( dl_y2 - dl_y1 ) / dl_l1 ) * ( ( dl_x3 - dl_x2 ) / dl_l2 ) - ( ( ( dl_y3 - dl_y2 ) / dl_l2 ) * ( dl_x2 / dl_l1 ) ) ) ) ) + sk_ref"
equation "d3442 = ( ( ( ( ( ( dl_y2 - dl_y1 ) / dl_l1 * ( -pod_w / 2 ) + dl_x2 / dl_l1 * ( -dl_y1 ) + dl_fo + fr_w ) ) * ( ( dl_x3 - dl_x2 ) / dl_l2 ) - ( ( ( ( dl_y3 - dl_y2 ) / dl_l2 * ( -pod_w / 2 + dl_x2 ) + ( dl_x3 - dl_x2 ) / dl_l2 * ( -dl_y2 ) + dl_fo + fr_w ) ) * ( dl_x2 / dl_l1 ) ) ) / ( ( ( dl_y2 - dl_y1 ) / dl_l1 ) * ( ( dl_x3 - dl_x2 ) / dl_l2 ) - ( ( ( dl_y3 - dl_y2 ) / dl_l2 ) * ( dl_x2 / dl_l1 ) ) ) ) ) + sk_ref"
equation "d3443 = ( ( ( ( ( dl_y1 + fr_w ) ) * ( dl_x2 / dl_l1 ) - ( -( ( ( dl_y2 - dl_y1 ) / dl_l1 * ( -pod_w / 2 ) + dl_x2 / dl_l1 * ( -dl_y1 ) + dl_fo + fr_w ) ) ) ) / ( -( -( ( dl_y2 - dl_y1 ) / dl_l1 ) ) ) ) ) + sk_ref"
equation "d3444 = ( ( ( -( ( ( dl_y2 - dl_y1 ) / dl_l1 ) * dl_y1 ) ) / ( -( -( ( dl_y2 - dl_y1 ) / dl_l1 ) ) ) ) ) + sk_ref"
equation "d3445 = ( ( ( ( ( dl_y2 - dl_y1 ) / dl_l1 ) * ( ( ( dl_y3 - dl_y2 ) / dl_l2 * ( -pod_w / 2 + dl_x2 ) + ( dl_x3 - dl_x2 ) / dl_l2 * ( -dl_y2 ) + dl_fo ) ) - ( ( ( dl_y3 - dl_y2 ) / dl_l2 ) * ( ( ( dl_y2 - dl_y1 ) / dl_l1 * ( -pod_w / 2 ) + dl_x2 / dl_l1 * ( -dl_y1 ) + dl_fo ) ) ) ) / ( ( ( dl_y2 - dl_y1 ) / dl_l1 ) * ( ( dl_x3 - dl_x2 ) / dl_l2 ) - ( ( ( dl_y3 - dl_y2 ) / dl_l2 ) * ( dl_x2 / dl_l1 ) ) ) ) ) + sk_ref"
equation "d3446 = ( ( ( ( ( dl_y2 - dl_y1 ) / dl_l1 ) * ( ( ( dl_y3 - dl_y2 ) / dl_l2 * ( -pod_w / 2 + dl_x2 ) + ( dl_x3 - dl_x2 ) / dl_l2 * ( -dl_y2 ) + dl_fo + fr_w ) ) - ( ( ( dl_y3 - dl_y2 ) / dl_l2 ) * ( ( ( dl_y2 - dl_y1 ) / dl_l1 * ( -pod_w / 2 ) + dl_x2 / dl_l1 * ( -dl_y1 ) + dl_fo + fr_w ) ) ) ) / ( ( ( dl_y2 - dl_y1 ) / dl_l1 ) * ( ( dl_x3 - dl_x2 ) / dl_l2 ) - ( ( ( dl_y3 - dl_y2 ) / dl_l2 ) * ( dl_x2 / dl_l1 ) ) ) ) ) + sk_ref"
equation "d3447 = ( ( ( -( ( ( dl_y2 - dl_y1 ) / dl_l1 ) * ( ( dl_y1 + fr_w ) ) ) ) / ( -( -( ( dl_y2 - dl_y1 ) / dl_l1 ) ) ) ) ) + sk_ref"
equation "d3448 = ( wall_z0 ) * ( 1 )"
equation "d3449 = ( wall_z0 + fr_w ) - ( wall_z0 )"
equation "d3451 = fr_t"
equation "d3452 = sk_ref"
equation "d3453 = sk_ref"
equation "d3454 = ( ( ( ( ( ( dl_y2 - dl_y1 ) / dl_l1 * ( -pod_w / 2 ) + dl_x2 / dl_l1 * ( -dl_y1 ) + dl_fo ) ) * ( ( dl_x3 - dl_x2 ) / dl_l2 ) - ( ( ( ( dl_y3 - dl_y2 ) / dl_l2 * ( -pod_w / 2 + dl_x2 ) + ( dl_x3 - dl_x2 ) / dl_l2 * ( -dl_y2 ) + dl_fo ) ) * ( dl_x2 / dl_l1 ) ) ) / ( ( ( dl_y2 - dl_y1 ) / dl_l1 ) * ( ( dl_x3 - dl_x2 ) / dl_l2 ) - ( ( ( dl_y3 - dl_y2 ) / dl_l2 ) * ( dl_x2 / dl_l1 ) ) ) ) ) + sk_ref"
equation "d3455 = ( ( ( -( ( ( -( -pod_w / 2 + dl_w ) + dl_fo + fr_w ) ) * ( ( dl_x3 - dl_x2 ) / dl_l2 ) ) ) / ( -( -( ( dl_x3 - dl_x2 ) / dl_l2 ) ) ) ) ) + sk_ref"
equation "d3456 = ( ( ( ( ( ( dl_y2 - dl_y1 ) / dl_l1 * ( -pod_w / 2 ) + dl_x2 / dl_l1 * ( -dl_y1 ) + dl_fo + fr_w ) ) * ( ( dl_x3 - dl_x2 ) / dl_l2 ) - ( ( ( ( dl_y3 - dl_y2 ) / dl_l2 * ( -pod_w / 2 + dl_x2 ) + ( dl_x3 - dl_x2 ) / dl_l2 * ( -dl_y2 ) + dl_fo + fr_w ) ) * ( dl_x2 / dl_l1 ) ) ) / ( ( ( dl_y2 - dl_y1 ) / dl_l1 ) * ( ( dl_x3 - dl_x2 ) / dl_l2 ) - ( ( ( dl_y3 - dl_y2 ) / dl_l2 ) * ( dl_x2 / dl_l1 ) ) ) ) ) + sk_ref"
equation "d3457 = ( ( ( ( ( dl_y2 - dl_y1 ) / dl_l1 ) * ( ( ( dl_y3 - dl_y2 ) / dl_l2 * ( -pod_w / 2 + dl_x2 ) + ( dl_x3 - dl_x2 ) / dl_l2 * ( -dl_y2 ) + dl_fo ) ) - ( ( ( dl_y3 - dl_y2 ) / dl_l2 ) * ( ( ( dl_y2 - dl_y1 ) / dl_l1 * ( -pod_w / 2 ) + dl_x2 / dl_l1 * ( -dl_y1 ) + dl_fo ) ) ) ) / ( ( ( dl_y2 - dl_y1 ) / dl_l1 ) * ( ( dl_x3 - dl_x2 ) / dl_l2 ) - ( ( ( dl_y3 - dl_y2 ) / dl_l2 ) * ( dl_x2 / dl_l1 ) ) ) ) ) + sk_ref"
equation "d3458 = ( ( ( ( ( dl_y3 - dl_y2 ) / dl_l2 ) * ( ( -( -pod_w / 2 + dl_w ) + dl_fo + fr_w ) ) - ( -( ( ( dl_y3 - dl_y2 ) / dl_l2 * ( -pod_w / 2 + dl_x2 ) + ( dl_x3 - dl_x2 ) / dl_l2 * ( -dl_y2 ) + dl_fo ) ) ) ) / ( -( -( ( dl_x3 - dl_x2 ) / dl_l2 ) ) ) ) ) + sk_ref"
equation "d3459 = ( ( ( ( ( dl_y3 - dl_y2 ) / dl_l2 ) * ( ( -( -pod_w / 2 + dl_w ) + dl_fo + fr_w ) ) - ( -( ( ( dl_y3 - dl_y2 ) / dl_l2 * ( -pod_w / 2 + dl_x2 ) + ( dl_x3 - dl_x2 ) / dl_l2 * ( -dl_y2 ) + dl_fo + fr_w ) ) ) ) / ( -( -( ( dl_x3 - dl_x2 ) / dl_l2 ) ) ) ) ) + sk_ref"
equation "d3460 = ( ( ( ( ( dl_y2 - dl_y1 ) / dl_l1 ) * ( ( ( dl_y3 - dl_y2 ) / dl_l2 * ( -pod_w / 2 + dl_x2 ) + ( dl_x3 - dl_x2 ) / dl_l2 * ( -dl_y2 ) + dl_fo + fr_w ) ) - ( ( ( dl_y3 - dl_y2 ) / dl_l2 ) * ( ( ( dl_y2 - dl_y1 ) / dl_l1 * ( -pod_w / 2 ) + dl_x2 / dl_l1 * ( -dl_y1 ) + dl_fo + fr_w ) ) ) ) / ( ( ( dl_y2 - dl_y1 ) / dl_l1 ) * ( ( dl_x3 - dl_x2 ) / dl_l2 ) - ( ( ( dl_y3 - dl_y2 ) / dl_l2 ) * ( dl_x2 / dl_l1 ) ) ) ) ) + sk_ref"
equation "d3461 = ( wall_z0 ) * ( 1 )"